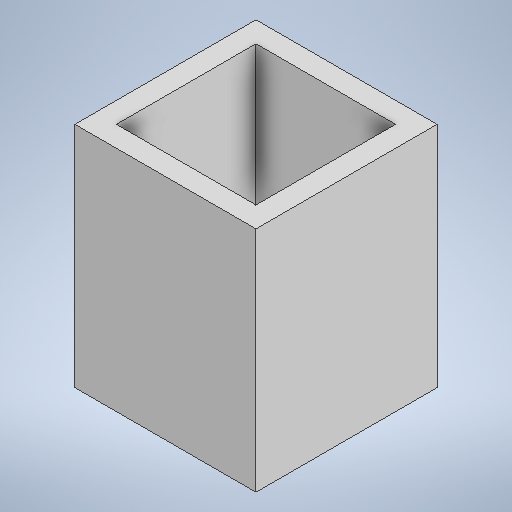
# Autodesk Inventor part: TAPA
Saved by Autodesk Inventor 2025.3 (Build 293356030, 356C)
## iProperties
Created: 2026-06-04
Part Number: TAPA
Material: Generic
Document SubType Name: Modeling
Designer: pablo
Density: 1 g/cm^3
Appearance: Default
Author: pablo
Autodesk Inventor part; units mm, degrees
ref_plane "YZ Plane" through (0, 0, 0) normal (1, 0, 0) x (0, 1, 0)
ref_plane "XZ Plane" through (0, 0, 0) normal (0, 1, 0) x (-1, 0, 0)
ref_plane "XY Plane" through (0, 0, 0) normal (0, 0, 1) x (1, 0, 0)
sketch "Sketch1" plane through (0, 0, 0) normal (0, 1, 0) x (-1, 0, 0)
  line L0 (-10.1, 10.1) -> (10.1, 10.1)
  line L1 (10.1, 10.1) -> (10.1, -10.1)
  line L2 (10.1, -10.1) -> (-10.1, -10.1)
  line L3 (-10.1, -10.1) -> (-10.1, 10.1)
  line L4 (-10.1, 10.1) -> (10.1, -10.1) construction
  line L5 (10.1, 10.1) -> (-10.1, -10.1) construction
  line L6 (13.1, 13.1) -> (-13.1, 13.1)
  line L7 (-13.1, 13.1) -> (-13.1, -13.1)
  line L8 (-13.1, -13.1) -> (13.1, -13.1)
  line L9 (13.1, -13.1) -> (13.1, 13.1)
  line L10 (13.1, 13.1) -> (-13.1, -13.1) construction
  line L11 (-13.1, 13.1) -> (13.1, -13.1) construction
  point P0 (0, 0)
  dimension "d0" = 20.2
  dimension "d1" = 3
  dimension "d2" = 3
  constraints: 24 end point, 4 midpoint, 4 parallel, 3 perpendicular, 2 horizontal
  measures "d0" distance of L1.end L2.end
  measures "d1" distance between parallel lines of L1 L9
  measures "d2" distance between parallel lines of L8 L2
extrude "Extrusion1" add sketch "Sketch1" along normal blind 3 contours L0 L1 L2 L3 | L9 L8 L7 L6
sketch "Sketch2" plane through (0, 3, 0) normal (0, 1, 0) x (1, 0, 0)
  line L0 (13.1, -13.1) -> (13.1, 13.1) projected
  line L1 (13.1, 13.1) -> (-13.1, 13.1) projected
  line L2 (-13.1, 13.1) -> (-13.1, -13.1) projected
  line L3 (-13.1, -13.1) -> (13.1, -13.1) projected
  line L4 (-10.1, -10.1) -> (10.1, -10.1)
  line L5 (10.1, -10.1) -> (10.1, 10.1)
  line L6 (10.1, 10.1) -> (-10.1, 10.1)
  line L7 (-10.1, 10.1) -> (-10.1, -10.1)
  line L8 (-10.1, -10.1) -> (10.1, 10.1) construction
  line L9 (10.1, -10.1) -> (-10.1, 10.1) construction
  point P0 (0, 0)
  dimension "d5" = 20.2
  dimension "d6" = 20.2
  constraints: 12 end point, 2 midpoint, 2 parallel, 1 horizontal, 1 perpendicular
  measures "d5" distance of L6.end L4.start
  measures "d6" distance of L5.end L6.end
extrude "Extrusion2" add sketch "Sketch2" along normal blind 30
body "Solid1"
